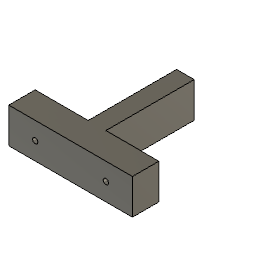
bracket v1 (Autodesk Fusion 360 design; units mm, degrees)
Autodesk Fusion 360 part; units mm, degrees
sketch "Sketch1" plane through (0, 0, 0) normal (0, 0, 1) x (1, 0, 0)
  line L0 (0, 0) -> (70, 0)
  line L1 (70, 0) -> (70, 15)
  line L2 (70, 15) -> (0, 15)
  line L3 (0, 15) -> (0, 0)
  line L4 (30, 15) -> (40, 15)
  line L5 (40, 15) -> (40, 65)
  line L6 (40, 65) -> (30, 65)
  line L7 (30, 65) -> (30, 15)
  dimension "d1" = 70
  dimension "d2" = 15
  dimension "d3" = 10
  dimension "d4" = 50
  dimension "d5" = 30
  constraint horizontal L0
  constraint vertical L1
  constraint horizontal L2
  constraint vertical L3
  constraint coincident L0.start L3.end
  constraint horizontal L4
  constraint vertical L5
  constraint horizontal L6
  constraint vertical L7
  constraint coincident L2 L4.start
  measures "d1" distance of L0.start L0.end
  measures "d2" distance of L0.start L2.end
  measures "d3" distance of L4.start L4.end
  measures "d4" distance of L4.start L6.end
  measures "d5" distance of L3 L7
extrude "Extrude1" add sketch "Sketch1" along normal blind 20
sketch "Sketch2" plane through (0, 15, 0) normal (0, 1, 0) x (-1, 0, 0)
  line L0 (-30, 0) -> (0, 0)
  line L1 (0, 0) -> (0, 20)
  line L2 (0, 20) -> (-30, 20)
  line L3 (-30, 20) -> (-30, 0)
  circle A0 centre (-15, 10) radius 1.5
  circle A1 centre (-15, 10) radius 3
  circle A2 centre (-55, 10) radius 1.5
  circle A3 centre (-55, 10) radius 3
  line L4 (-70, 0) -> (-40, 0)
  line L5 (-70, 0) -> (-70, 20)
  dimension "d8" = 3
  dimension "d9" = 6
  dimension "d10" = 3
  dimension "d11" = 6
  dimension "d12" = 10
  dimension "d13" = 10
  dimension "d14" = 15
  dimension "d15" = 15
  constraint concentric A0 A1
  constraint concentric A2 A3
  measures "d8" diameter of A0
  measures "d9" diameter of A1
  measures "d10" diameter of A2
  measures "d11" diameter of A3
  measures "d12" distance of L0 A0.centre
  measures "d13" distance of A2.centre L4
  measures "d14" distance of L1 A0.centre
  measures "d15" distance of A2.centre L5
extrude "Extrude2" cut sketch "Sketch2" against normal blind 40 contours A0 | A2
extrude "Extrude3" cut sketch "Sketch2" against normal blind 3 contours A1 | A3
equation "d5 = ( 70 / 2 ) * 1 mm - 5 mm"
